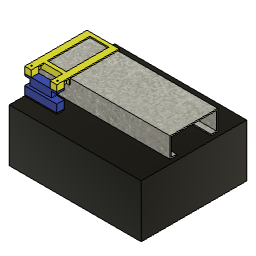
Garage Sensor Bracket v5 (Autodesk Fusion 360 design; units mm, degrees)
Autodesk Fusion 360 part; units mm, degrees
note: some values were not read from the file. Set by a fixed rule: which face or edge a step refers to.
sketch "Sketch1" plane through (0, 0, 0) normal (1, 0, 0) x (0, 1, 0)
  line L0 (0, 0) -> (72.4, 0)
  line L1 (72.4, 0) -> (72.4, 30.8)
  line L2 (72.4, 30.8) -> (0, 30.8)
  line L3 (0, 30.8) -> (0, 0)
  line L4 (-43.8, -6.4) -> (116.2, -6.4)
  line L5 (116.2, -6.4) -> (116.2, -86.4)
  line L6 (116.2, -86.4) -> (-43.8, -86.4)
  line L7 (-43.8, -86.4) -> (-43.8, -6.4)
  line L8 (0, 0) -> (72.4, 0) construction
  line L9 (72.4, 0) -> (72.4, -6.4) construction
  line L10 (72.4, -6.4) -> (0, -6.4) construction
  line L11 (0, -6.4) -> (0, 0) construction
  line L12 (-20.47, -6.4) -> (-9.07, -6.4)
  line L13 (-9.07, -6.4) -> (-9.07, 7.1)
  line L14 (-9.07, 7.1) -> (-20.47, 7.1)
  line L15 (-20.47, 7.1) -> (-20.47, -6.4)
  line L16 (-20.47, -6.4) -> (-9.07, -6.4)
  line L17 (-9.07, -6.4) -> (-9.07, -4.62)
  line L18 (-9.07, -4.62) -> (-20.47, -4.62)
  line L19 (-20.47, -4.62) -> (-20.47, -6.4)
  line L20 (-20.47, 7.1) -> (-9.07, 7.1)
  line L21 (-9.07, 7.1) -> (-9.07, 11.1)
  line L22 (-9.07, 11.1) -> (-20.47, 11.1)
  line L23 (-20.47, 11.1) -> (-20.47, 7.1)
  line L24 (-20.47, 11.1) -> (-9.07, 11.1)
  line L25 (-9.07, 11.1) -> (-9.07, 22.82)
  line L26 (-9.07, 22.82) -> (-20.47, 22.82)
  line L27 (-20.47, 22.82) -> (-20.47, 11.1)
  line L28 (70.6, 29) -> (1.8, 29)
  line L29 (1.8, 29) -> (1.8, 1.8)
  line L30 (1.8, 1.8) -> (70.6, 1.8)
  line L31 (70.6, 1.8) -> (70.6, 29)
  line L32 (10, 1.8) -> (10, 0)
  line L33 (62.4, 1.8) -> (62.4, 0)
  line L34 (-9.07, 22.82) -> (72.4, 22.82)
  line L35 (-20.47, 22.82) -> (74.07, 22.82)
  line L36 (74.07, 22.82) -> (74.07, 32.6)
  line L37 (74.07, 32.6) -> (-20.47, 32.6)
  line L38 (-20.47, 32.6) -> (-20.47, 22.82)
  line L39 (-1.67, 22.82) -> (-1.67, 32.6)
  line L40 (-9.07, 22.82) -> (-9.07, 32.6)
  line L41 (0, 30.8) -> (-9.07, 30.8)
  dimension "d1" = 72.4
  dimension "d2" = 30.8
  dimension "d3" = 160
  dimension "d4" = 80
  dimension "d5" = 72.4
  dimension "d6" = 6.4
  dimension "d7" = 11.4
  dimension "d8" = 13.5
  dimension "d9" = 1.78
  dimension "d10" = 20.47
  dimension "d11" = 4
  dimension "d12" = 11.72
  dimension "d13" = -1.8
  dimension "d14" = 10
  dimension "d15" = 10
  dimension "d16" = 1.8
  dimension "d17" = 1.67
  dimension "d20" = 1.67
  constraint horizontal L0
  constraint vertical L1
  constraint horizontal L2
  constraint vertical L3
  constraint coincident L0.start L3.end
  constraint horizontal L4
  constraint vertical L5
  constraint horizontal L6
  constraint vertical L7
  constraint horizontal L8
  constraint vertical L9
  constraint horizontal L10
  constraint vertical L11
  constraint midpoint L4 L10
  constraint horizontal L12
  constraint vertical L13
  constraint horizontal L14
  constraint vertical L15
  constraint coincident L4 L12.start
  constraint horizontal L16
  constraint vertical L17
  constraint horizontal L18
  constraint vertical L19
  constraint collinear L13 L17
  constraint horizontal L20
  constraint vertical L21
  constraint horizontal L22
  constraint vertical L23
  constraint collinear L13 L21
  constraint horizontal L24
  constraint vertical L25
  constraint horizontal L26
  constraint vertical L27
  constraint collinear L13 L25
  constraint coincident L30 L32.start
  constraint coincident L0 L32.end
  constraint perpendicular L0 L32
  constraint coincident L30 L33.start
  constraint coincident L8 L33.end
  constraint perpendicular L8 L33
  constraint coincident L1 L34.end
  constraint perpendicular L1 L34
  constraint horizontal L35
  constraint vertical L36
  constraint horizontal L37
  constraint vertical L38
  constraint coincident L35 L39.start
  constraint coincident L37 L39.end
  constraint perpendicular L37 L39
  constraint coincident L37 L40.end
  constraint perpendicular L37 L40
  constraint coincident L40 L41.end
  constraint perpendicular L40 L41
  measures "d1" distance of L0.start L0.end
  measures "d2" distance of L0.start L2.end
  measures "d3" distance of L4.start L4.end
  measures "d4" distance of L4.start L6.end
  measures "d5" distance of L0.start L0.end
  measures "d6" distance of L0.start L10.end
  measures "d7" distance of L12.start L12.end
  measures "d8" distance of L12.start L14.end
  measures "d9" distance of L12.start L18.end
  measures "d10" distance of L3 L15
  measures "d11" distance of L14.end L22.end
  measures "d12" distance of L22.end L26.end
  measures "d14" distance of L3 L32.start
  measures "d15" distance of L1 L33
  measures "d16" distance of L2 L37
  measures "d17" distance of L1 L36
  measures "d20" distance of L3 L39
extrude "Extrude1" add sketch "Sketch1" along normal blind 200 contours L4 L5 L6 L7 L12 L16 makes body 1 in component "Motor"
extrude "Extrude1'" add sketch "Sketch1" along normal blind 200 separate body contours L0 L3 L29 L30 L32 L34 L35 | L1 L2 L3 L28 L29 L31 L34 L35 | L0 L1 L30 L31 L33 L34 L35 makes body 2 in component "Rail"
extrude "Extrude1''" add sketch "Sketch1" along normal blind 48.7 separate body contours L4 L12 L13 L15 L16 L17 L18 L19 makes body 3 in component "Adhesive"
extrude "Extrude1'''" add sketch "Sketch1" along normal up to surface (48.7 mm away) separate body contours L13 L14 L15 L18 L20 makes body 4 in component "Lower Sensor"
extrude "Extrude1''''" add sketch "Sketch1" along normal up to surface (48.7 mm away) separate body contours L22 L24 L25 L26 L27 L35 makes body 5 in component "Upper Sensor"
extrude "Extrude1'''''" add sketch "Sketch1" along normal up to surface (48.7 mm away) separate body contours L3 L34 L35 L39 L41 | L1 L2 L35 L36 L37 L39 L41 | L37 L39 L40 L41 | L26 L35 L37 L38 L40 makes body 6 in component "Sensor Bracket"
sketch "Sketch1 (2)" plane through (0, -20.47, 0) normal (0, -1, 0) x (1, 0, 0) in component "Upper Sensor"
  line L0 (48.7, 11.1) -> (48.7, 22.82)
  line L1 (48.7, 22.82) -> (0, 22.82)
  line L2 (0, 22.82) -> (0, 11.1)
  line L3 (0, 11.1) -> (48.7, 11.1)
  line L4 (0, 22.82) -> (48.7, 22.82)
  line L5 (48.7, 22.82) -> (48.7, 19.96)
  line L6 (48.7, 19.96) -> (0, 19.96)
  line L7 (0, 19.96) -> (0, 22.82)
  line L8 (24.35, 22.82) -> (24.35, 11.1) construction
  line L9 (8.1, 19.96) -> (40.6, 19.96)
  line L10 (40.6, 19.96) -> (40.6, 11.1)
  line L11 (40.6, 11.1) -> (8.1, 11.1)
  line L12 (8.1, 11.1) -> (8.1, 19.96)
  line L13 (24.35, 19.96) -> (24.35, 11.1) construction
  dimension "d33" = 2.86
  dimension "d34" = 32.5
  constraint horizontal L4
  constraint vertical L5
  constraint horizontal L6
  constraint vertical L7
  constraint coincident L0 L5.end
  constraint coincident L1.end L2.start
  constraint midpoint L4 L8.start
  constraint midpoint L3 L8.end
  constraint horizontal L9
  constraint vertical L10
  constraint horizontal L11
  constraint vertical L12
  constraint coincident L3 L10.end
  constraint coincident L6 L9.start
  constraint midpoint L9 L13.start
  constraint midpoint L11 L8.end
  constraint collinear L8 L13
  measures "d33" distance of L1.end L6.end
  measures "d34" distance of L10 L12
extrude "Extrude2" cut sketch "Sketch1 (2)" against normal up to surface (11.4 mm away) contours L0 L3 L6 L10 | L2 L3 L6 L12 bodies 5 in component "Upper Sensor"
sketch "Sketch2" plane through (0, 0, 19.96) normal (0, 0, -1) x (1, 0, 0) in component "Upper Sensor"
  line L0 (0, 9.07) -> (8.1, 9.07)
  line L1 (8.1, 9.07) -> (8.1, 20.47)
  line L2 (8.1, 20.47) -> (0, 20.47)
  line L3 (0, 20.47) -> (0, 9.07)
  circle A0 centre (4.615, 14.77) radius 1.87
  line L4 (40.6, 9.07) -> (48.7, 9.07) construction
  line L5 (48.7, 9.07) -> (48.7, 20.47) construction
  line L6 (48.7, 20.47) -> (40.6, 20.47) construction
  line L7 (40.6, 20.47) -> (40.6, 9.07) construction
  line L8 (0, 14.77) -> (48.7, 14.77) construction
  circle A1 centre (44.085, 14.77) radius 1.87
  line L9 (4.615, 14.77) -> (0, 14.77)
  line L10 (44.085, 14.77) -> (48.7, 14.77)
  dimension "d37" = 3.74
  dimension "d38" = 3.74
  dimension "d39" = 39.47
  constraint midpoint L3 L8.start
  constraint midpoint L5 L8.end
  constraint coincident A0.centre L8
  constraint coincident L8 A1.centre
  constraint coincident A0.centre L9.start
  constraint perpendicular L3 L9
  constraint coincident A1.centre L10.start
  constraint equal L9 L10
  measures "d37" diameter of A0
  measures "d38" diameter of A1
  measures "d39" distance of A0.centre A1.centre
extrude "Extrude3" cut sketch "Sketch2" against normal up to surface (2.86 mm away) contours A0 | A1 bodies 5 in component "Upper Sensor"
sketch "Sketch1 (3)" plane through (0, 0, 22.82) normal (0, 0, -1) x (1, 0, 0) in component "Sensor Bracket"
  line L0 (48.7, 9.07) -> (48.7, 20.47)
  line L1 (48.7, 20.47) -> (0, 20.47)
  line L2 (0, 20.47) -> (0, 9.07)
  line L3 (0, 9.07) -> (48.7, 9.07)
  circle A0 centre (4.615, 14.77) radius 1.87 construction
  circle A1 centre (44.085, 14.77) radius 1.87 construction
  circle A2 centre (4.615, 14.77) radius 1
  circle A3 centre (44.085, 14.77) radius 1
  line L4 (0, -74.07) -> (48.7, -74.07) construction
  line L5 (0, -72.4) -> (48.7, -72.4)
  line L6 (10, 20.47) -> (38.7, 20.47)
  line L7 (38.7, 20.47) -> (38.7, -72.4)
  line L8 (38.7, -72.4) -> (10, -72.4)
  line L9 (10, -72.4) -> (10, 20.47)
  line L10 (48.7, 0) -> (48.7, 1.67)
  line L11 (48.7, 1.67) -> (0, 1.67)
  line L12 (0, 1.67) -> (0, 0)
  line L13 (0, 0) -> (48.7, 0)
  line L14 (10, -4) -> (38.7, -4)
  line L15 (10, -68.4) -> (38.7, -68.4)
  line L16 (10, 5.67) -> (38.7, 5.67) construction
  dimension "d42" = 2
  dimension "d43" = 2
  dimension "d44" = 10
  dimension "d45" = 10
  dimension "d46" = 4
  dimension "d47" = 4
  dimension "d48" = 4
  constraint concentric A0 A2
  constraint concentric A1 A3
  constraint horizontal L6
  constraint vertical L7
  constraint horizontal L8
  constraint vertical L9
  constraint coincident L5 L7.end
  constraint coincident L1 L6.start
  constraint coincident L9 L14.start
  constraint coincident L7 L14.end
  constraint perpendicular L7 L14
  constraint coincident L9 L15.start
  constraint coincident L7 L15.end
  constraint perpendicular L7 L15
  constraint coincident L9 L16.start
  constraint coincident L7 L16.end
  constraint perpendicular L7 L16
  measures "d42" diameter of A2
  measures "d43" diameter of A3
  measures "d44" distance of L2 L9
  measures "d45" distance of L0 L7
  measures "d46" distance of L13 L14
  measures "d47" distance of L8 L15
  measures "d48" distance of L11 L16
extrude "Extrude2'" cut sketch "Sketch1 (3)" against normal up to surface (9.78 mm away) contours L3 L7 L9 L11 | L1 L3 L6 L7 L9 | L7 L9 L14 L15 | A2 | A3 bodies 6 in component "Sensor Bracket"
sketch "Sketch2 (2)" plane through (0, 0, 30.8) normal (0, 0, -1) x (1, 0, 0) in component "Sensor Bracket"
  line L0 (10, 1.67) -> (10, 9.07)
  line L1 (10, 9.07) -> (0, 9.07)
  line L2 (0, 9.07) -> (0, 1.67)
  line L3 (0, 1.67) -> (10, 1.67)
  line L4 (48.7, 0) -> (48.7, 1.67)
  line L5 (48.7, 1.67) -> (0, 1.67)
  line L6 (0, 1.67) -> (0, 0)
  line L7 (0, 0) -> (48.7, 0)
  line L8 (24.35, 1.67) -> (24.35, 0) construction
  line L9 (4.165, 9.07) -> (5.835, 9.07)
  line L10 (5.835, 9.07) -> (5.835, 1.67)
  line L11 (5.835, 1.67) -> (4.165, 1.67)
  line L12 (4.165, 1.67) -> (4.165, 9.07)
  line L13 (44.535, 1.67) -> (44.535, 9.07)
  line L14 (44.535, 9.07) -> (42.865, 9.07)
  line L15 (42.865, 9.07) -> (42.865, 1.67)
  line L16 (42.865, 1.67) -> (44.535, 1.67)
  dimension "d51" = 1.67
  constraint midpoint L5 L8.start
  constraint midpoint L7 L8.end
  constraint horizontal L9
  constraint vertical L10
  constraint horizontal L11
  constraint vertical L12
  constraint coincident L3 L10.end
  constraint coincident L1 L9.start
  constraint midpoint L1 L9
  constraint symmetric L8 L9.start L13.end
  constraint symmetric L8 L9.end L14.end
  constraint symmetric L8 L10.end L15.end
  constraint symmetric L8 L11.end L13.start
  measures "d51" distance of L9.start L9.end
extrude "Extrude3'" add sketch "Sketch2 (2)" along normal up to surface (7.98 mm away) contours L1 L3 L5 L9 L10 L11 L12 | L5 L13 L14 L15 L16 bodies 6 in component "Sensor Bracket"
component "Motor" placed x (1, 0, 0) y (0, 1, 0) z (0, 0, 1) at (0, 0, 0)
component "Rail" placed x (1, 0, 0) y (0, 1, 0) z (0, 0, 1) at (0, 0, 0)
component "Adhesive" placed x (1, 0, 0) y (0, 1, 0) z (0, 0, 1) at (0, 0, 0)
component "Lower Sensor" placed x (1, 0, 0) y (0, 1, 0) z (0, 0, 1) at (0, 0, 0)
component "Upper Sensor" placed x (1, 0, 0) y (0, 1, 0) z (0, 0, 1) at (0, 0, 0)
component "Sensor Bracket" placed x (1, 0, 0) y (0, 1, 0) z (0, 0, 1) at (0, 0, 0)
equation "d5 = d1"
equation "d6 = 37.2 mm - 30.8 mm"
equation "d9 = 13.5 mm - 11.72 mm"
equation "d15 = d14"
equation "d16 = plate_thick"
equation "d17 = wall_thick"
equation "wall_thick = 1.67 mm"
equation "plate_thick = 1.8 mm"
equation "d20 = wall_thick"
equation "d38 = d37"
equation "d39 = 43.21 mm - 3.74 mm"
equation "d47 = d46"
equation "d48 = d46"
equation "d51 = wall_thick"
